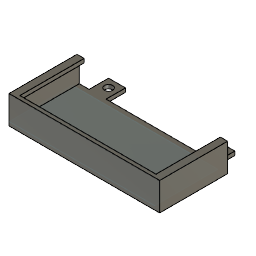
Soft starter mount (Autodesk Fusion 360 design; units mm, degrees)
Autodesk Fusion 360 part; units mm, degrees
sketch "Sketch1" plane through (0, 0, 0) normal (0, 0, 1) x (1, 0, 0)
  line L0 (0, 0) -> (60, 0)
  line L1 (60, 0) -> (60, 26)
  line L2 (60, 26) -> (0, 26)
  line L3 (0, 26) -> (0, 0)
  dimension "d1" = 60
  dimension "d2" = 26
  constraint horizontal L0
  constraint vertical L1
  constraint horizontal L2
  constraint vertical L3
  constraint coincident L0.start L3.end
  measures "d1" distance of L0.start L0.end
  measures "d2" distance of L0.start L2.end
extrude "Extrude1" add sketch "Sketch1" along normal blind 1.6
sketch "Sketch2" plane through (0, 0, 1.6) normal (0, 0, 1) x (-1, 0, 0)
  line L0 (0, -26) -> (0, 0)
  line L1 (0, 0) -> (-60, 0)
  line L2 (-60, 0) -> (-60, -26)
  line L3 (-60, -26) -> (0, -26)
extrude "Extrude2" add 1 faces at (60, 8.6667, 0.5333) along direction (1, 0, 0) blind 2
extrude "Extrude3" add 1 faces at (20.6667, 26, 0.5333) along direction (0, 1, 0) blind 2
sketch "Sketch3" plane through (0, 0, 1.6) normal (0, 0, 1) x (-1, 0, 0)
  line L0 (0, -28) -> (-1, -28)
  line L1 (-1, -28) -> (-1, 0)
  line L2 (-1, 0) -> (0, 0)
  line L3 (0, 0) -> (0, -28)
  line L4 (-62, -28) -> (-61, -28)
  line L5 (-61, -28) -> (-61, 0)
  line L6 (-61, 0) -> (-62, 0)
  line L7 (-62, 0) -> (-62, -28)
  line L8 (0, 0) -> (-62, 0)
  line L9 (-62, 0) -> (-62, -1.5)
  line L10 (-62, -1.5) -> (0, -1.5)
  line L11 (0, -1.5) -> (0, 0)
  dimension "d9" = 1.5
  constraint horizontal L0
  constraint vertical L1
  constraint horizontal L2
  constraint vertical L3
  constraint horizontal L4
  constraint vertical L5
  constraint horizontal L6
  constraint vertical L7
  constraint horizontal L8
  constraint vertical L9
  constraint horizontal L10
  constraint vertical L11
  constraint coincident L2.end L3.start
  measures "d9" distance of L2.end L10.end
extrude "Extrude4" add sketch "Sketch3" along normal blind 10
sketch "Sketch4" plane through (1, 0, 0) normal (1, 0, 0) x (0, 1, 0)
  line L0 (1.5, 1.6) -> (28, 1.6)
  line L1 (28, 1.6) -> (28, 11.6)
  line L2 (28, 11.6) -> (1.5, 11.6)
  line L3 (1.5, 11.6) -> (1.5, 1.6)
  line L4 (28, 11.6) -> (0, 11.6)
  line L5 (0, 11.6) -> (0, 10)
  line L6 (0, 10) -> (28, 10)
  line L7 (28, 10) -> (28, 11.6)
  constraint horizontal L4
  constraint vertical L5
  constraint horizontal L6
  constraint vertical L7
  constraint coincident L1.end L2.start
extrude "Extrude5" add sketch "Sketch4" along normal blind 2 contours L1 L2 L3 L4 L6 L7
sketch "Sketch5" plane through (61, 0, 0) normal (-1, 0, 0) x (0, -1, 0)
  line L0 (-28, 1.6) -> (-1.5, 1.6)
  line L1 (-1.5, 1.6) -> (-1.5, 11.6)
  line L2 (-1.5, 11.6) -> (-28, 11.6)
  line L3 (-28, 11.6) -> (-28, 1.6)
  line L4 (-28, 11.6) -> (0, 11.6)
  line L5 (0, 11.6) -> (0, 10)
  line L6 (0, 10) -> (-28, 10)
  line L7 (-28, 10) -> (-28, 11.6)
  dimension "d14" = 1.6
  constraint horizontal L4
  constraint vertical L5
  constraint horizontal L6
  constraint vertical L7
  constraint coincident L2.end L3.start
  measures "d14" distance of L2.end L6.end
extrude "Extrude6" add sketch "Sketch5" along normal blind 2 contours L1 L2 L3 L4 L6 L7
sketch "Sketch6" plane through (0, 28, 0) normal (0, 1, 0) x (-1, 0, 0)
  line L0 (-62, 0) -> (0, 0)
  line L1 (0, 0) -> (0, 11.6)
  line L2 (0, 11.6) -> (-3, 11.6)
  line L3 (-3, 11.6) -> (-3, 10)
  line L4 (-3, 10) -> (-1, 10)
  line L5 (-1, 10) -> (-1, 1.6)
  line L6 (-1, 1.6) -> (-61, 1.6)
  line L7 (-61, 1.6) -> (-61, 10)
  line L8 (-61, 10) -> (-59, 10)
  line L9 (-59, 10) -> (-59, 11.6)
  line L10 (-59, 11.6) -> (-62, 11.6)
  line L11 (-62, 11.6) -> (-62, 0)
  line L12 (0, 0) -> (-5, 0)
  line L13 (-62, 0) -> (-57, 0)
  line L14 (-57, 0) -> (-50, 0)
  line L15 (-50, 0) -> (-50, 1.6)
  line L16 (-50, 1.6) -> (-57, 1.6)
  line L17 (-57, 1.6) -> (-57, 0)
  line L18 (-5, 0) -> (-12, 0)
  line L19 (-12, 0) -> (-12, 1.6)
  line L20 (-12, 1.6) -> (-5, 1.6)
  line L21 (-5, 1.6) -> (-5, 0)
  dimension "d17" = 5
  dimension "d18" = 7
  dimension "d19" = 1.6
  dimension "d20" = 7
  dimension "d21" = 1.6
  constraint coincident L0.end L1.start
  constraint coincident L0 L12.end
  constraint coincident L0.start L11.end
  constraint perpendicular L11 L13
  constraint horizontal L14
  constraint vertical L15
  constraint horizontal L16
  constraint vertical L17
  constraint horizontal L18
  constraint vertical L19
  constraint horizontal L20
  constraint vertical L21
  measures "d17" distance of L0.start L13.end
  measures "d18" distance of L13.end L14.end
  measures "d19" distance of L13.end L16.end
  measures "d20" distance of L12.end L18.end
  measures "d21" distance of L12.end L20.end
extrude "Extrude7" add sketch "Sketch6" along normal blind 8 contours L0 L6 L14 L15 L16 L17 | L0 L6 L18 L19 L20 L21
sketch "Sketch7" plane through (0, 0, 1.6) normal (0, 0, 1) x (-1, 0, 0)
  line L0 (-61, -1.5) -> (-61, -28)
  line L1 (-61, -28) -> (-57, -28)
  line L2 (-57, -28) -> (-57, -36)
  line L3 (-57, -36) -> (-50, -36)
  line L4 (-50, -36) -> (-50, -28)
  line L5 (-50, -28) -> (-12, -28)
  line L6 (-12, -28) -> (-12, -36)
  line L7 (-12, -36) -> (-5, -36)
  line L8 (-5, -36) -> (-5, -28)
  line L9 (-5, -28) -> (-1, -28)
  line L10 (-1, -28) -> (-1, -1.5)
  line L11 (-1, -1.5) -> (-61, -1.5)
  line L12 (-5, -36) -> (-12, -29)
  line L13 (-12, -36) -> (-5, -29)
  line L14 (-50, -36) -> (-57, -29)
  line L15 (-57, -36) -> (-50, -29)
  circle A0 centre (-8.5, -32.5) radius 1.7
  circle A1 centre (-53.5, -32.5) radius 1.7
  dimension "d24" = 3.4
  dimension "d25" = 3.4
  constraint coincident L7.end L8.start
  constraint coincident L6 L12.end
  constraint coincident L6.end L7.start
  constraint coincident L8 L13.end
  constraint perpendicular L12 L13
  constraint coincident L3.end L4.start
  constraint coincident L2 L14.end
  constraint perpendicular L13 L14
  constraint coincident L2.end L3.start
  constraint coincident L4 L15.end
  constraint perpendicular L14 L15
  constraint midpoint L13 A0.centre
  constraint midpoint L14 A1.centre
  measures "d24" diameter of A0
  measures "d25" diameter of A1
extrude "Extrude8" cut sketch "Sketch7" against normal blind 1.6 contours L14 L15 A1 | L14 L15 A1 | L14 L15 A1 | L14 L15 A1 | L12 L13 A0 | L12 L13 A0 | L12 L13 A0 | L12 L13 A0
